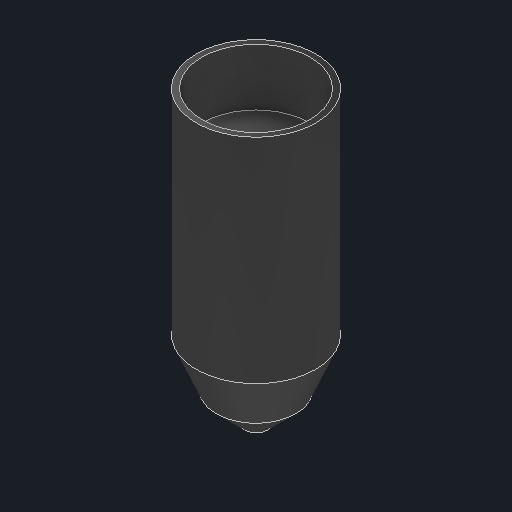
# Autodesk Inventor part: tripod_foot
Saved by Autodesk Inventor 2027.1 (Build 311270010, 270A)
## iProperties
Created: 2026-11-04
Part Number: tripod_foot
Material: Generic
Description: Leg foot / spike cap
Document SubType Name: Modeling
Designer: Claude (from photos)
Density: 1 g/cm^3
Appearance: Glossy - Black
Author: alexg
Autodesk Inventor part; units mm, degrees
ref_plane "YZ Plane" through (0, 0, 0) normal (1, 0, 0) x (0, 1, 0)
ref_plane "XZ Plane" through (0, 0, 0) normal (0, 1, 0) x (-1, 0, 0)
ref_plane "XY Plane" through (0, 0, 0) normal (0, 0, 1) x (1, 0, 0)
sketch "Foot sketch" plane through (0, 0, 0) normal (0, 0, 1) x (1, 0, 0)
  line L0 (0, -780) -> (0, -862)
  line L1 (0, -862) -> (4, -862)
  line L2 (4, -862) -> (14, -852)
  line L3 (14, -852) -> (21, -835)
  line L4 (21, -835) -> (21, -760)
  line L5 (21, -760) -> (19, -760)
  line L6 (19, -760) -> (19, -780)
  line L7 (19, -780) -> (0, -780)
  constraints: 16 end point
revolve "Foot" add sketch "Foot sketch" angle 360 about axis through (0, -780, 0) along (0, -1, 0)
body "Solid1"
